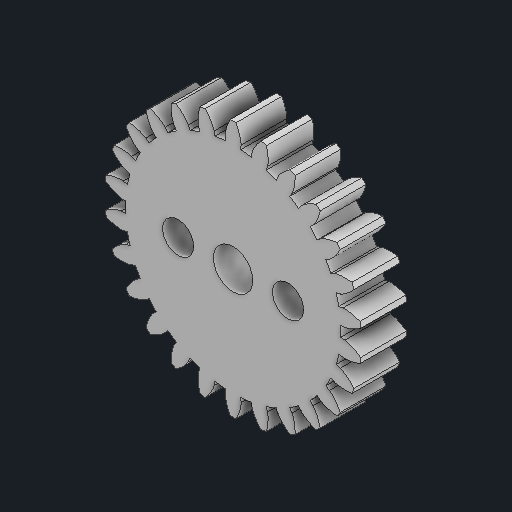
# Autodesk Inventor part: P2-03 Right driven gear 26 teeth
Saved by Autodesk Inventor 2027.1 (Build 311270010, 270A)
## iProperties
Created: 2026-10-21
Part Number: P2-03 Right driven gear 26 teeth
Material: Generic
Document SubType Name: Modeling
Designer: anshi
Mass: 2.32572 g
Surface Area: 20.3436 cm^2
Volume: 2.32572 cm^3
Density: 1 g/cm^3
Appearance: Default
Author: anshi
Autodesk Inventor part; units mm, degrees
ref_plane "YZ Plane" through (0, 0, 0) normal (1, 0, 0) x (0, 1, 0)
ref_plane "XZ Plane" through (0, 0, 0) normal (0, 1, 0) x (-1, 0, 0)
ref_plane "XY Plane" through (0, 0, 0) normal (0, 0, 1) x (1, 0, 0)
sketch "Dimensioned base profile" plane through (0, 0, 0) normal (0, 0, 1) x (1, 0, 0)
  line L0 (11.7357, 0.5797) -> (12.2011, 0.6027)
  spline S0 degree 4 poles (12.2011, 0.6027) (12.209, 0.6028) (12.2485, 0.6066) (12.3141, 0.6172) (12.4241, 0.6414) (12.5388, 0.6724) (12.6782, 0.7169) (12.8402, 0.7771) (13.0239, 0.8551) (13.3144, 0.9948) (13.5707, 1.1408) (13.7787, 1.2746) (13.9317, 1.3813) knots 0 0 0 0 0 0.103317 0.164454 0.235729 0.315759 0.40363 0.498674 0.600371 0.708303 1 1 1 1 1
  arc A0 (13.9317, 1.3813) -> (13.8574, 1.9929) centre (0, 0) ccw
  spline S1 degree 4 poles (13.8574, 1.9929) (13.6835, 2.0597) (13.4498, 2.1397) (13.1663, 2.2199) (12.851, 2.2859) (12.6541, 2.3177) (12.4826, 2.3373) (12.3366, 2.3472) (12.2176, 2.35) (12.1048, 2.3474) (12.0382, 2.342) (11.9988, 2.3366) (11.9908, 2.3347) knots 0 0 0 0 0 0.291394 0.399224 0.500833 0.595807 0.683628 0.763634 0.834917 0.896108 1 1 1 1 1
  line L1 (11.9908, 2.3347) -> (11.5334, 2.2457)
  arc A1 (11.5334, 2.2457) -> (11.2559, 3.3714) centre (0, 0) ccw
  line L2 (11.2559, 3.3714) -> (11.7023, 3.5051)
  spline S2 degree 4 poles (11.7023, 3.5051) (11.7102, 3.5074) (11.7477, 3.5207) (11.8092, 3.5469) (11.9104, 3.5968) (12.0145, 3.6545) (12.1392, 3.7311) (12.282, 3.8282) (12.4416, 3.9478) (12.69, 4.1528) (12.9037, 4.3557) (13.0734, 4.5352) (13.1963, 4.6753) knots 0 0 0 0 0 0.103853 0.165057 0.23635 0.316361 0.404186 0.49916 0.60077 0.708601 1 1 1 1 1
  arc A2 (13.1963, 4.6753) -> (12.9778, 5.2513) centre (0, 0) ccw
  spline S3 degree 4 poles (12.9778, 5.2513) (12.7925, 5.2741) (12.5459, 5.2953) (12.2508, 5.3048) (11.9284, 5.2928) (11.7294, 5.2763) (11.558, 5.2542) (11.414, 5.2289) (11.2981, 5.2033) (11.1899, 5.1741) (11.1272, 5.1536) (11.0907, 5.1394) (11.0837, 5.1365) knots 0 0 0 0 0 0.292086 0.400157 0.501975 0.597116 0.685051 0.765101 0.836335 0.897338 1 1 1 1 1
  line L3 (11.0837, 5.1365) -> (10.6608, 4.9405)
  arc A3 (10.6608, 4.9405) -> (10.122, 5.9672) centre (0, 0) ccw
  line L4 (10.122, 5.9672) -> (10.5235, 6.2038)
  spline S4 degree 4 poles (10.5235, 6.2038) (10.5305, 6.2079) (10.5638, 6.2298) (10.6172, 6.2699) (10.7036, 6.3426) (10.7908, 6.4235) (10.8936, 6.5277) (11.009, 6.6562) (11.1353, 6.8106) (11.3275, 7.069) (11.4864, 7.3171) (11.6082, 7.5321) (11.694, 7.6975) knots 0 0 0 0 0 0.10386 0.165064 0.236357 0.316368 0.404191 0.499165 0.600774 0.708603 1 1 1 1 1
  arc A4 (11.694, 7.6975) -> (11.344, 8.2045) centre (0, 0) ccw
  spline S5 degree 4 poles (11.344, 8.2045) (11.1586, 8.1822) (10.9139, 8.1436) (10.6251, 8.0821) (10.3149, 7.9932) (10.1256, 7.9295) (9.9645, 7.867) (9.8307, 7.808) (9.7244, 7.7554) (9.6264, 7.7014) (9.5704, 7.6665) (9.5385, 7.6442) (9.5323, 7.6397) knots 0 0 0 0 0 0.29219 0.400296 0.502144 0.597307 0.685255 0.765304 0.83652 0.89748 1 1 1 1 1
  line L5 (9.5323, 7.6397) -> (9.1687, 7.3483)
  arc A5 (9.1687, 7.3483) -> (8.3999, 8.2161) centre (0, 0) ccw
  line L6 (8.3999, 8.2161) -> (8.733, 8.542)
  spline S6 degree 4 poles (8.733, 8.542) (8.7389, 8.5476) (8.7659, 8.5768) (8.8082, 8.6286) (8.8747, 8.7199) (8.94, 8.8193) (9.0149, 8.945) (9.0962, 9.0974) (9.1819, 9.2775) (9.3066, 9.5744) (9.4015, 9.8534) (9.4684, 10.0912) (9.512, 10.2724) knots 0 0 0 0 0 0.10386 0.165064 0.236356 0.316367 0.404191 0.499164 0.600774 0.708603 1 1 1 1 1
  arc A6 (9.512, 10.2724) -> (9.0509, 10.6809) centre (0, 0) ccw
  spline S7 degree 4 poles (9.0509, 10.6809) (8.8761, 10.6147) (8.6477, 10.5185) (8.3819, 10.3893) (8.1018, 10.2286) (7.9332, 10.1213) (7.7918, 10.0221) (7.676, 9.9328) (7.5854, 9.8564) (7.5034, 9.7808) (7.4575, 9.7337) (7.4319, 9.7048) (7.427, 9.699) knots 0 0 0 0 0 0.292397 0.400574 0.50248 0.597687 0.68566 0.765709 0.836892 0.897771 1 1 1 1 1
  line L7 (7.427, 9.699) -> (7.1437, 9.329)
  arc A7 (7.1437, 9.329) -> (6.1895, 9.9876) centre (0, 0) ccw
  line L8 (6.1895, 9.9876) -> (6.435, 10.3837)
  spline S8 degree 4 poles (6.435, 10.3837) (6.4394, 10.3906) (6.4587, 10.4253) (6.4874, 10.4857) (6.5301, 10.5902) (6.5698, 10.7024) (6.6123, 10.8424) (6.6548, 11.0098) (6.6949, 11.2052) (6.7449, 11.5234) (6.7703, 11.8169) (6.7782, 12.0639) (6.7773, 12.2502) knots 0 0 0 0 0 0.103831 0.16503 0.236321 0.316331 0.404157 0.499134 0.600748 0.708584 1 1 1 1 1
  arc A8 (6.7773, 12.2502) -> (6.2318, 12.5365) centre (0, 0) ccw
  spline S9 degree 4 poles (6.2318, 12.5365) (6.0775, 12.4303) (5.8783, 12.2819) (5.6505, 12.0925) (5.4166, 11.8691) (5.2783, 11.7244) (5.1646, 11.5942) (5.0737, 11.4798) (5.0042, 11.3841) (4.9432, 11.2915) (4.9103, 11.2351) (4.8931, 11.2013) (4.8901, 11.1945) knots 0 0 0 0 0 0.292948 0.401308 0.503368 0.59869 0.686732 0.766794 0.837914 0.898616 1 1 1 1 1
  line L9 (4.8901, 11.1945) -> (4.7036, 10.7675)
  arc A9 (4.7036, 10.7675) -> (3.6195, 11.1786) centre (0, 0) ccw
  line L10 (3.6195, 11.1786) -> (3.763, 11.622)
  spline S10 degree 4 poles (3.763, 11.622) (3.7657, 11.6296) (3.7762, 11.668) (3.7897, 11.7334) (3.8062, 11.845) (3.8179, 11.9634) (3.8257, 12.1096) (3.8268, 12.2823) (3.819, 12.4816) (3.7914, 12.8026) (3.7456, 13.0937) (3.6942, 13.3355) (3.6487, 13.5162) knots 0 0 0 0 0 0.10378 0.164969 0.236254 0.316264 0.404092 0.499076 0.600699 0.708547 1 1 1 1 1
  arc A10 (3.6487, 13.5162) -> (3.0505, 13.6636) centre (0, 0) ccw
  spline S11 degree 4 poles (3.0505, 13.6636) (2.9262, 13.5237) (2.7683, 13.3323) (2.5925, 13.0943) (2.4188, 12.8216) (2.3193, 12.6482) (2.24, 12.4945) (2.1791, 12.3617) (2.1345, 12.252) (2.0974, 12.147) (2.0789, 12.0842) (2.0703, 12.0468) (2.069, 12.0395) knots 0 0 0 0 0 0.292693 0.400968 0.502958 0.59823 0.686248 0.766317 0.837488 0.898305 1 1 1 1 1
  line L11 (2.069, 12.0395) -> (1.9901, 11.5802)
  arc A11 (1.9901, 11.5802) -> (0.8391, 11.72) centre (0, 0) ccw
  line L12 (0.8391, 11.72) -> (0.8724, 12.1848)
  spline S12 degree 4 poles (0.8724, 12.1848) (0.8731, 12.1929) (0.874, 12.2327) (0.8714, 12.2994) (0.8606, 12.4118) (0.8436, 12.5295) (0.8163, 12.6733) (0.7761, 12.8413) (0.7208, 13.0329) (0.6172, 13.3379) (0.5032, 13.6097) (0.3955, 13.8321) (0.308, 13.9966) knots 0 0 0 0 0 0.103807 0.165003 0.236292 0.316303 0.404131 0.499111 0.600729 0.708569 1 1 1 1 1
  arc A12 (0.308, 13.9966) -> (-0.308, 13.9966) centre (0, 0) ccw
  spline S13 degree 4 poles (-0.308, 13.9966) (-0.3956, 13.831) (-0.5034, 13.6073) (-0.6175, 13.3341) (-0.7212, 13.0277) (-0.7766, 12.8355) (-0.8168, 12.6673) (-0.8441, 12.5237) (-0.8611, 12.4066) (-0.8717, 12.2958) (-0.8743, 12.2305) (-0.8732, 12.1921) (-0.8724, 12.1848) knots 0 0 0 0 0 0.292789 0.401092 0.503102 0.598385 0.686404 0.766465 0.837615 0.898399 1 1 1 1 1
  line L13 (-0.8724, 12.1848) -> (-0.8391, 11.72)
  arc A13 (-0.8391, 11.72) -> (-1.9901, 11.5802) centre (0, 0) ccw
  line L14 (-1.9901, 11.5802) -> (-2.069, 12.0395)
  spline S14 degree 4 poles (-2.069, 12.0395) (-2.0704, 12.0475) (-2.0791, 12.0864) (-2.0977, 12.1506) (-2.1351, 12.2571) (-2.1798, 12.3673) (-2.2408, 12.5004) (-2.32, 12.6538) (-2.4195, 12.8267) (-2.593, 13.098) (-2.7686, 13.3346) (-2.9263, 13.5248) (-3.0505, 13.6636) knots 0 0 0 0 0 0.103844 0.165049 0.236343 0.316356 0.404182 0.499158 0.600769 0.7086 1 1 1 1 1
  arc A14 (-3.0505, 13.6636) -> (-3.6487, 13.5162) centre (0, 0) ccw
  spline S15 degree 4 poles (-3.6487, 13.5162) (-3.6942, 13.3348) (-3.7456, 13.0922) (-3.7913, 12.8001) (-3.8189, 12.4782) (-3.8268, 12.2785) (-3.8256, 12.1056) (-3.8178, 11.9595) (-3.8062, 11.8415) (-3.7898, 11.7309) (-3.7764, 11.6665) (-3.7659, 11.6289) (-3.763, 11.622) knots 0 0 0 0 0 0.292364 0.400522 0.502409 0.597597 0.685557 0.765608 0.836813 0.897752 1 1 1 1 1
  line L15 (-3.763, 11.622) -> (-3.6195, 11.1786)
  arc A15 (-3.6195, 11.1786) -> (-4.7036, 10.7675) centre (0, 0) ccw
  line L16 (-4.7036, 10.7675) -> (-4.8901, 11.1945)
  spline S16 degree 4 poles (-4.8901, 11.1945) (-4.8935, 11.2019) (-4.9112, 11.2375) (-4.9447, 11.2953) (-5.0065, 11.3897) (-5.0763, 11.4861) (-5.1673, 11.6007) (-5.281, 11.7307) (-5.4189, 11.8748) (-5.6523, 12.0967) (-5.8794, 12.2845) (-6.078, 12.4314) (-6.2318, 12.5365) knots 0 0 0 0 0 0.103783 0.164983 0.236278 0.316296 0.404129 0.499113 0.600734 0.708575 1 1 1 1 1
  arc A16 (-6.2318, 12.5365) -> (-6.7773, 12.2502) centre (0, 0) ccw
  spline S17 degree 4 poles (-6.7773, 12.2502) (-6.7783, 12.0637) (-6.7704, 11.8165) (-6.7451, 11.5226) (-6.6952, 11.2041) (-6.6551, 11.0085) (-6.6127, 10.8411) (-6.5701, 10.7011) (-6.5305, 10.589) (-6.4878, 10.4848) (-6.459, 10.4248) (-6.4396, 10.3902) (-6.435, 10.3837) knots 0 0 0 0 0 0.29167 0.399589 0.501273 0.596303 0.68416 0.764178 0.835443 0.896575 1 1 1 1 1
  line L17 (-6.435, 10.3837) -> (-6.1895, 9.9876)
  arc A17 (-6.1895, 9.9876) -> (-7.1437, 9.329) centre (0, 0) ccw
  line L18 (-7.1437, 9.329) -> (-7.427, 9.699)
  spline S18 degree 4 poles (-7.427, 9.699) (-7.4321, 9.7052) (-7.4579, 9.7355) (-7.5042, 9.7835) (-7.5868, 9.8603) (-7.6776, 9.9371) (-7.7935, 10.0266) (-7.9349, 10.1257) (-8.1033, 10.2325) (-8.383, 10.3923) (-8.6484, 10.5203) (-8.8764, 10.6155) (-9.0509, 10.6809) knots 0 0 0 0 0 0.103669 0.164859 0.236155 0.31618 0.404024 0.499024 0.600662 0.708522 1 1 1 1 1
  arc A18 (-9.0509, 10.6809) -> (-9.512, 10.2724) centre (0, 0) ccw
  spline S19 degree 4 poles (-9.512, 10.2724) (-9.4684, 10.0912) (-9.4015, 9.8534) (-9.3067, 9.5744) (-9.1819, 9.2774) (-9.0962, 9.0973) (-9.015, 8.9449) (-8.9401, 8.8192) (-8.8748, 8.7198) (-8.8083, 8.6285) (-8.766, 8.5768) (-8.7389, 8.5476) (-8.733, 8.542) knots 0 0 0 0 0 0.291403 0.399234 0.500844 0.595818 0.683642 0.763651 0.834942 0.896144 1 1 1 1 1
  line L19 (-8.733, 8.542) -> (-8.3999, 8.2161)
  arc A19 (-8.3999, 8.2161) -> (-9.1687, 7.3483) centre (0, 0) ccw
  line L20 (-9.1687, 7.3483) -> (-9.5323, 7.6397)
  spline S20 degree 4 poles (-9.5323, 7.6397) (-9.5388, 7.6443) (-9.571, 7.6675) (-9.6275, 7.7029) (-9.726, 7.7576) (-9.8325, 7.8104) (-9.9664, 7.8696) (-10.1274, 7.932) (-10.3166, 7.9955) (-10.6264, 8.0838) (-10.9147, 8.1447) (-11.1589, 8.1827) (-11.344, 8.2045) knots 0 0 0 0 0 0.103491 0.164665 0.235961 0.315996 0.403859 0.498882 0.600548 0.708439 1 1 1 1 1
  arc A20 (-11.344, 8.2045) -> (-11.694, 7.6975) centre (0, 0) ccw
  spline S21 degree 4 poles (-11.694, 7.6975) (-11.6081, 7.5322) (-11.486, 7.3173) (-11.3269, 7.0693) (-11.1345, 6.8109) (-11.0081, 6.6566) (-10.8927, 6.5282) (-10.7899, 6.424) (-10.7028, 6.3431) (-10.6165, 6.2703) (-10.5634, 6.2301) (-10.5302, 6.2082) (-10.5235, 6.2038) knots 0 0 0 0 0 0.291491 0.399357 0.501 0.596005 0.683854 0.763882 0.835179 0.896367 1 1 1 1 1
  line L21 (-10.5235, 6.2038) -> (-10.122, 5.9672)
  arc A21 (-10.122, 5.9672) -> (-10.6608, 4.9405) centre (0, 0) ccw
  line L22 (-10.6608, 4.9405) -> (-11.0837, 5.1365)
  spline S22 degree 4 poles (-11.0837, 5.1365) (-11.091, 5.1395) (-11.1278, 5.1544) (-11.1911, 5.1752) (-11.2998, 5.2048) (-11.4159, 5.2306) (-11.56, 5.256) (-11.7313, 5.278) (-11.9302, 5.2944) (-12.2521, 5.306) (-12.5467, 5.2961) (-12.7929, 5.2745) (-12.9778, 5.2513) knots 0 0 0 0 0 0.103496 0.164668 0.235961 0.315994 0.403855 0.498878 0.600543 0.708435 1 1 1 1 1
  arc A22 (-12.9778, 5.2513) -> (-13.1963, 4.6753) centre (0, 0) ccw
  spline S23 degree 4 poles (-13.1963, 4.6753) (-13.0729, 4.5355) (-12.9024, 4.3564) (-12.688, 4.154) (-12.4389, 3.9495) (-12.279, 3.83) (-12.136, 3.733) (-12.0113, 3.6565) (-11.9075, 3.5987) (-11.8069, 3.5487) (-11.7464, 3.522) (-11.7091, 3.5086) (-11.7023, 3.5051) knots 0 0 0 0 0 0.291864 0.399868 0.501639 0.596753 0.684688 0.764768 0.83607 0.897187 1 1 1 1 1
  line L23 (-11.7023, 3.5051) -> (-11.2559, 3.3714)
  arc A23 (-11.2559, 3.3714) -> (-11.5334, 2.2457) centre (0, 0) ccw
  line L24 (-11.5334, 2.2457) -> (-11.9908, 2.3347)
  spline S24 degree 4 poles (-11.9908, 2.3347) (-11.9985, 2.3358) (-12.0378, 2.3414) (-12.1041, 2.3464) (-12.2167, 2.3491) (-12.3355, 2.3464) (-12.4815, 2.3365) (-12.6531, 2.3169) (-12.8501, 2.2853) (-13.1656, 2.2195) (-13.4494, 2.1395) (-13.6834, 2.0596) (-13.8574, 1.9929) knots 0 0 0 0 0 0.103266 0.164415 0.235705 0.31575 0.403633 0.498685 0.600387 0.708319 1 1 1 1 1
  arc A24 (-13.8574, 1.9929) -> (-13.9317, 1.3813) centre (0, 0) ccw
  spline S25 degree 4 poles (-13.9317, 1.3813) (-13.7781, 1.2751) (-13.5694, 1.1419) (-13.3123, 0.9966) (-13.0211, 0.8575) (-12.8371, 0.7798) (-12.675, 0.7198) (-12.5356, 0.6753) (-12.4212, 0.6441) (-12.3119, 0.6197) (-12.2474, 0.6084) (-12.2081, 0.6042) (-12.2011, 0.6027) knots 0 0 0 0 0 0.292307 0.400465 0.502368 0.597589 0.685599 0.765713 0.836996 0.898019 1 1 1 1 1
  line L25 (-12.2011, 0.6027) -> (-11.7357, 0.5797)
  arc A25 (-11.7357, 0.5797) -> (-11.7357, -0.5797) centre (0, 0) ccw
  line L26 (-11.7357, -0.5797) -> (-12.2011, -0.6027)
  spline S26 degree 4 poles (-12.2011, -0.6027) (-12.2088, -0.6037) (-12.2483, -0.6077) (-12.3138, -0.6187) (-12.4237, -0.6431) (-12.5383, -0.6742) (-12.6778, -0.7187) (-12.8397, -0.7788) (-13.0235, -0.8566) (-13.3141, -0.9959) (-13.5705, -1.1415) (-13.7786, -1.2749) (-13.9317, -1.3813) knots 0 0 0 0 0 0.103188 0.164331 0.235624 0.315674 0.403567 0.498629 0.600343 0.708288 1 1 1 1 1
  arc A26 (-13.9317, -1.3813) -> (-13.8574, -1.9929) centre (0, 0) ccw
  spline S27 degree 4 poles (-13.8574, -1.9929) (-13.6831, -2.0601) (-13.4487, -2.1405) (-13.1646, -2.2212) (-12.8487, -2.2876) (-12.6514, -2.3195) (-12.4797, -2.3392) (-12.3337, -2.3491) (-12.215, -2.3517) (-12.1028, -2.3488) (-12.0371, -2.343) (-11.9979, -2.3372) (-11.9908, -2.3347) knots 0 0 0 0 0 0.292101 0.400169 0.501981 0.597114 0.685046 0.765101 0.836358 0.897413 1 1 1 1 1
  line L27 (-11.9908, -2.3347) -> (-11.5334, -2.2457)
  arc A27 (-11.5334, -2.2457) -> (-11.2559, -3.3714) centre (0, 0) ccw
  line L28 (-11.2559, -3.3714) -> (-11.7023, -3.5051)
  spline S28 degree 4 poles (-11.7023, -3.5051) (-11.7074, -3.5058) (-11.7442, -3.519) (-11.8016, -3.5435) (-11.9002, -3.5923) (-12.0031, -3.6494) (-12.1278, -3.726) (-12.2711, -3.8233) (-12.4319, -3.9435) (-12.6829, -4.1496) (-12.8993, -4.3537) (-13.0715, -4.5343) (-13.1963, -4.6753) knots 0 0 0 0 0 0.097727 0.158305 0.22951 0.309802 0.398187 0.493943 0.596511 0.705442 1 1 1 1 1
  arc A28 (-13.1963, -4.6753) -> (-12.9778, -5.2513) centre (0, 0) ccw
  spline S29 degree 4 poles (-12.9778, -5.2513) (-12.7923, -5.2747) (-12.5453, -5.2965) (-12.2499, -5.3067) (-11.9271, -5.2954) (-11.7278, -5.2791) (-11.5564, -5.2571) (-11.4122, -5.2318) (-11.2965, -5.2059) (-11.1885, -5.1763) (-11.1264, -5.1552) (-11.0898, -5.1403) (-11.0837, -5.1365) knots 0 0 0 0 0 0.292369 0.400531 0.502425 0.597627 0.685608 0.765689 0.836938 0.897938 1 1 1 1 1
  line L29 (-11.0837, -5.1365) -> (-10.6608, -4.9405)
  arc A29 (-10.6608, -4.9405) -> (-10.122, -5.9672) centre (0, 0) ccw
  line L30 (-10.122, -5.9672) -> (-10.5235, -6.2038)
  spline S30 degree 4 poles (-10.5235, -6.2038) (-10.5278, -6.2051) (-10.5603, -6.2269) (-10.6094, -6.2638) (-10.6929, -6.3344) (-10.7789, -6.4143) (-10.8817, -6.5185) (-10.9976, -6.6474) (-11.1252, -6.8027) (-11.32, -7.0633) (-11.4818, -7.3136) (-11.6062, -7.5305) (-11.694, -7.6975) knots 0 0 0 0 0 0.096349 0.156803 0.228 0.308361 0.396873 0.492802 0.595581 0.704753 1 1 1 1 1
  arc A30 (-11.694, -7.6975) -> (-11.344, -8.2045) centre (0, 0) ccw
  spline S31 degree 4 poles (-11.344, -8.2045) (-11.1583, -8.1826) (-10.9132, -8.1444) (-10.6239, -8.0833) (-10.3132, -7.9947) (-10.1236, -7.9311) (-9.9624, -7.8687) (-9.8285, -7.8096) (-9.7224, -7.7569) (-9.6247, -7.7025) (-9.5695, -7.6675) (-9.5375, -7.6444) (-9.5323, -7.6397) knots 0 0 0 0 0 0.292525 0.400746 0.502694 0.597942 0.685959 0.766062 0.837313 0.898283 1 1 1 1 1
  line L31 (-9.5323, -7.6397) -> (-9.1687, -7.3483)
  arc A31 (-9.1687, -7.3483) -> (-8.3999, -8.2161) centre (0, 0) ccw
  line L32 (-8.3999, -8.2161) -> (-8.733, -8.542)
  spline S32 degree 4 poles (-8.733, -8.542) (-8.7356, -8.5466) (-8.7619, -8.5756) (-8.8005, -8.6251) (-8.865, -8.7144) (-8.9294, -8.8131) (-9.0043, -8.9389) (-9.086, -9.0914) (-9.1729, -9.2722) (-9.2999, -9.5705) (-9.3974, -9.851) (-9.4666, -10.0902) (-9.512, -10.2724) knots 0 0 0 0 0 0.098234 0.158888 0.230131 0.310429 0.39879 0.494491 0.596978 0.705801 1 1 1 1 1
  arc A32 (-9.512, -10.2724) -> (-9.0509, -10.6809) centre (0, 0) ccw
  spline S33 degree 4 poles (-9.0509, -10.6809) (-8.876, -10.6154) (-8.6475, -10.5201) (-8.3816, -10.3919) (-8.1013, -10.232) (-7.9327, -10.125) (-7.7911, -10.0259) (-7.6753, -9.9365) (-7.5847, -9.8597) (-7.5025, -9.7832) (-7.4568, -9.7354) (-7.4313, -9.7052) (-7.427, -9.699) knots 0 0 0 0 0 0.292006 0.400046 0.501836 0.596954 0.684879 0.764936 0.836202 0.897278 1 1 1 1 1
  line L33 (-7.427, -9.699) -> (-7.1437, -9.329)
  arc A33 (-7.1437, -9.329) -> (-6.1895, -9.9876) centre (0, 0) ccw
  line L34 (-6.1895, -9.9876) -> (-6.435, -10.3837)
  spline S34 degree 4 poles (-6.435, -10.3837) (-6.4362, -10.3891) (-6.4549, -10.4235) (-6.4806, -10.4812) (-6.5219, -10.5835) (-6.5607, -10.6948) (-6.6034, -10.8348) (-6.6462, -11.0025) (-6.6873, -11.1987) (-6.7393, -11.5185) (-6.7668, -11.814) (-6.7767, -12.0626) (-6.7773, -12.2502) knots 0 0 0 0 0 0.098614 0.159305 0.230554 0.310837 0.399164 0.494819 0.597247 0.706002 1 1 1 1 1
  arc A34 (-6.7773, -12.2502) -> (-6.2318, -12.5365) centre (0, 0) ccw
  spline S35 degree 4 poles (-6.2318, -12.5365) (-6.0778, -12.4312) (-5.8789, -12.2839) (-5.6516, -12.0959) (-5.418, -11.8736) (-5.2798, -11.7294) (-5.1662, -11.5993) (-5.0751, -11.4847) (-5.0054, -11.3885) (-4.9439, -11.2944) (-4.9107, -11.2371) (-4.8931, -11.2016) (-4.8901, -11.1945) knots 0 0 0 0 0 0.291864 0.399856 0.501606 0.596695 0.6846 0.76465 0.835926 0.897032 1 1 1 1 1
  line L35 (-4.8901, -11.1945) -> (-4.7036, -10.7675)
  arc A35 (-4.7036, -10.7675) -> (-3.6195, -11.1786) centre (0, 0) ccw
  line L36 (-3.6195, -11.1786) -> (-3.763, -11.622)
  spline S36 degree 4 poles (-3.763, -11.622) (-3.763, -11.6273) (-3.7729, -11.6652) (-3.7841, -11.7271) (-3.7997, -11.8362) (-3.8107, -11.9535) (-3.8186, -12.0997) (-3.8201, -12.2728) (-3.813, -12.4731) (-3.7869, -12.7963) (-3.743, -13.0899) (-3.6931, -13.3338) (-3.6487, -13.5162) knots 0 0 0 0 0 0.098331 0.158995 0.23024 0.310535 0.398887 0.494578 0.597049 0.705854 1 1 1 1 1
  arc A36 (-3.6487, -13.5162) -> (-3.0505, -13.6636) centre (0, 0) ccw
  spline S37 degree 4 poles (-3.0505, -13.6636) (-2.9263, -13.5244) (-2.7686, -13.3338) (-2.5929, -13.0968) (-2.4194, -12.825) (-2.3199, -12.6519) (-2.2407, -12.4984) (-2.1797, -12.3654) (-2.135, -12.2553) (-2.0977, -12.1492) (-2.0791, -12.0857) (-2.0704, -12.047) (-2.069, -12.0395) knots 0 0 0 0 0 0.291857 0.399849 0.501601 0.596692 0.684601 0.764656 0.835936 0.897045 1 1 1 1 1
  line L37 (-2.069, -12.0395) -> (-1.9901, -11.5802)
  arc A37 (-1.9901, -11.5802) -> (-0.8391, -11.72) centre (0, 0) ccw
  line L38 (-0.8391, -11.72) -> (-0.8724, -12.1848)
  spline S38 degree 4 poles (-0.8724, -12.1848) (-0.8712, -12.1906) (-0.8717, -12.2298) (-0.8678, -12.2934) (-0.8568, -12.4036) (-0.8395, -12.5204) (-0.8122, -12.6642) (-0.7722, -12.8325) (-0.7173, -13.0251) (-0.6146, -13.3321) (-0.5016, -13.6061) (-0.3948, -13.8305) (-0.308, -13.9966) knots 0 0 0 0 0 0.099467 0.160239 0.231494 0.311733 0.39998 0.495525 0.597821 0.706426 1 1 1 1 1
  arc A38 (-0.308, -13.9966) -> (0.308, -13.9966) centre (0, 0) ccw
  spline S39 degree 4 poles (0.308, -13.9966) (0.3953, -13.8317) (0.5028, -13.6087) (0.6166, -13.3364) (0.72, -13.0309) (0.7752, -12.839) (0.8153, -12.671) (0.8427, -12.5272) (0.8598, -12.4097) (0.8706, -12.2979) (0.8735, -12.2319) (0.8727, -12.1923) (0.8724, -12.1848) knots 0 0 0 0 0 0.291972 0.400004 0.501792 0.596912 0.684843 0.764908 0.836185 0.897271 1 1 1 1 1
  line L39 (0.8724, -12.1848) -> (0.8391, -11.72)
  arc A39 (0.8391, -11.72) -> (1.9901, -11.5802) centre (0, 0) ccw
  line L40 (1.9901, -11.5802) -> (2.069, -12.0395)
  spline S40 degree 4 poles (2.069, -12.0395) (2.0713, -12.0455) (2.0801, -12.0838) (2.099, -12.1454) (2.1362, -12.2502) (2.1809, -12.3597) (2.2419, -12.4928) (2.321, -12.6466) (2.4204, -12.8202) (2.5936, -13.0932) (2.769, -13.3317) (2.9265, -13.5235) (3.0505, -13.6636) knots 0 0 0 0 0 0.100504 0.161375 0.232637 0.312821 0.400967 0.496378 0.598513 0.706936 1 1 1 1 1
  arc A40 (3.0505, -13.6636) -> (3.6487, -13.5162) centre (0, 0) ccw
  spline S41 degree 4 poles (3.6487, -13.5162) (3.6937, -13.335) (3.7445, -13.0927) (3.7894, -12.8008) (3.8164, -12.4793) (3.8239, -12.2797) (3.8226, -12.1069) (3.8147, -11.9608) (3.8033, -11.8427) (3.7872, -11.7318) (3.7746, -11.6673) (3.7645, -11.6291) (3.763, -11.622) knots 0 0 0 0 0 0.2922 0.400317 0.502181 0.597369 0.685351 0.765448 0.836727 0.897769 1 1 1 1 1
  line L41 (3.763, -11.622) -> (3.6195, -11.1786)
  arc A41 (3.6195, -11.1786) -> (4.7036, -10.7675) centre (0, 0) ccw
  line L42 (4.7036, -10.7675) -> (4.8901, -11.1945)
  spline S42 degree 4 poles (4.8901, -11.1945) (4.8939, -11.2009) (4.9117, -11.2362) (4.9452, -11.293) (5.0068, -11.3868) (5.0766, -11.4828) (5.1676, -11.5974) (5.2812, -11.7276) (5.4191, -11.872) (5.6524, -12.0947) (5.8794, -12.2832) (6.078, -12.4308) (6.2318, -12.5365) knots 0 0 0 0 0 0.102517 0.163593 0.23488 0.314966 0.402923 0.498074 0.599893 0.707956 1 1 1 1 1
  arc A42 (6.2318, -12.5365) -> (6.7773, -12.2502) centre (0, 0) ccw
  spline S43 degree 4 poles (6.7773, -12.2502) (6.7781, -12.0639) (6.7699, -11.8169) (6.7443, -11.5234) (6.694, -11.2052) (6.6538, -11.0098) (6.6113, -10.8424) (6.5687, -10.7024) (6.5291, -10.5902) (6.4866, -10.4858) (6.4582, -10.4255) (6.439, -10.3907) (6.435, -10.3837) knots 0 0 0 0 0 0.291508 0.399379 0.501027 0.596034 0.683885 0.763912 0.835207 0.896392 1 1 1 1 1
  line L43 (6.435, -10.3837) -> (6.1895, -9.9876)
  arc A43 (6.1895, -9.9876) -> (7.1437, -9.329) centre (0, 0) ccw
  line L44 (7.1437, -9.329) -> (7.427, -9.699)
  spline S44 degree 4 poles (7.427, -9.699) (7.4322, -9.704) (7.4579, -9.734) (7.5039, -9.7809) (7.586, -9.857) (7.6767, -9.9335) (7.7925, -10.023) (7.9339, -10.1222) (8.1025, -10.2295) (8.3824, -10.3901) (8.648, -10.5189) (8.8762, -10.6149) (9.0509, -10.6809) knots 0 0 0 0 0 0.102138 0.163175 0.234457 0.314561 0.402554 0.497754 0.599633 0.707764 1 1 1 1 1
  arc A44 (9.0509, -10.6809) -> (9.512, -10.2724) centre (0, 0) ccw
  spline S45 degree 4 poles (9.512, -10.2724) (9.4679, -10.0911) (9.4004, -9.8531) (9.3048, -9.574) (9.1794, -9.2769) (9.0934, -9.0967) (9.012, -8.9444) (8.9371, -8.8186) (8.872, -8.7193) (8.8061, -8.6284) (8.7647, -8.5769) (8.7379, -8.5477) (8.733, -8.542) knots 0 0 0 0 0 0.291937 0.39996 0.501744 0.596864 0.684798 0.764871 0.836157 0.897254 1 1 1 1 1
  line L45 (8.733, -8.542) -> (8.3999, -8.2161)
  arc A45 (8.3999, -8.2161) -> (9.1687, -7.3483) centre (0, 0) ccw
  line L46 (9.1687, -7.3483) -> (9.5323, -7.6397)
  spline S46 degree 4 poles (9.5323, -7.6397) (9.5387, -7.6448) (9.5709, -7.6681) (9.6274, -7.7038) (9.7261, -7.7588) (9.8326, -7.8117) (9.9665, -7.8708) (10.1275, -7.9332) (10.3167, -7.9965) (10.6265, -8.0846) (10.9148, -8.1452) (11.159, -8.1829) (11.344, -8.2045) knots 0 0 0 0 0 0.103849 0.165054 0.236348 0.31636 0.404185 0.499161 0.600771 0.708602 1 1 1 1 1
  arc A46 (11.344, -8.2045) -> (11.694, -7.6975) centre (0, 0) ccw
  spline S47 degree 4 poles (11.694, -7.6975) (11.608, -7.5321) (11.4859, -7.3173) (11.3267, -7.0693) (11.1342, -6.8109) (11.0078, -6.6566) (10.8923, -6.5281) (10.7895, -6.4239) (10.7024, -6.343) (10.6163, -6.2703) (10.5632, -6.2301) (10.5301, -6.2082) (10.5235, -6.2038) knots 0 0 0 0 0 0.291569 0.399462 0.50113 0.596155 0.684019 0.764055 0.83535 0.896523 1 1 1 1 1
  line L47 (10.5235, -6.2038) -> (10.122, -5.9672)
  arc A47 (10.122, -5.9672) -> (10.6608, -4.9405) centre (0, 0) ccw
  line L48 (10.6608, -4.9405) -> (11.0837, -5.1365)
  spline S48 degree 4 poles (11.0837, -5.1365) (11.0911, -5.1396) (11.1279, -5.1545) (11.1913, -5.1755) (11.3002, -5.2052) (11.4163, -5.231) (11.5604, -5.2564) (11.7317, -5.2784) (11.9305, -5.2948) (12.2524, -5.3062) (12.5469, -5.2962) (12.793, -5.2745) (12.9778, -5.2513) knots 0 0 0 0 0 0.103712 0.164907 0.236202 0.316225 0.404065 0.499059 0.600691 0.708543 1 1 1 1 1
  arc A48 (12.9778, -5.2513) -> (13.1963, -4.6753) centre (0, 0) ccw
  spline S49 degree 4 poles (13.1963, -4.6753) (13.0733, -4.5352) (12.9033, -4.3558) (12.6894, -4.153) (12.4407, -3.9481) (12.281, -3.8285) (12.1382, -3.7314) (12.0135, -3.6549) (11.9095, -3.5972) (11.8085, -3.5472) (11.7473, -3.521) (11.7099, -3.5076) (11.7023, -3.5051) knots 0 0 0 0 0 0.291576 0.39947 0.501138 0.596162 0.684024 0.764057 0.835348 0.896518 1 1 1 1 1
  line L49 (11.7023, -3.5051) -> (11.2559, -3.3714)
  arc A49 (11.2559, -3.3714) -> (11.5334, -2.2457) centre (0, 0) ccw
  line L50 (11.5334, -2.2457) -> (11.9908, -2.3347)
  spline S50 degree 4 poles (11.9908, -2.3347) (11.9987, -2.3365) (12.038, -2.3423) (12.1046, -2.3478) (12.2174, -2.3507) (12.3363, -2.3481) (12.4823, -2.3382) (12.6539, -2.3185) (12.8508, -2.2867) (13.1662, -2.2206) (13.4497, -2.1401) (13.6835, -2.0599) (13.8574, -1.9929) knots 0 0 0 0 0 0.103742 0.164925 0.236208 0.316219 0.40405 0.499039 0.600669 0.708524 1 1 1 1 1
  arc A50 (13.8574, -1.9929) -> (13.9317, -1.3813) centre (0, 0) ccw
  spline S51 degree 4 poles (13.9317, -1.3813) (13.7788, -1.2748) (13.571, -1.1412) (13.3149, -0.9955) (13.0246, -0.8561) (12.841, -0.7782) (12.6791, -0.7181) (12.5396, -0.6736) (12.4248, -0.6425) (12.3146, -0.6182) (12.2487, -0.6073) (12.2092, -0.6034) (12.2011, -0.6027) knots 0 0 0 0 0 0.291442 0.399289 0.500916 0.595906 0.683744 0.763765 0.835062 0.89626 1 1 1 1 1
  line L51 (12.2011, -0.6027) -> (11.7357, -0.5797)
  arc A51 (11.7357, -0.5797) -> (11.7357, 0.5797) centre (0, 0) ccw
  circle A52 centre (0, 0) radius 2.15
  circle A53 centre (-6, 0) radius 1.7
  circle A54 centre (6, 0) radius 1.7
  point P0 (12.214, 0.6036)
  point P1 (12.2533, 0.6083)
  point P2 (12.3185, 0.6192)
  point P3 (12.4093, 0.6389)
  point P4 (12.5248, 0.6696)
  point P5 (12.6642, 0.7137)
  point P6 (12.8264, 0.7735)
  point P7 (13.0102, 0.8512)
  point P8 (13.2142, 0.9488)
  point P9 (13.4369, 1.0685)
  point P10 (13.6767, 1.212)
  point P11 (13.5696, 2.096)
  point P12 (13.3028, 2.1778)
  point P13 (13.0581, 2.2405)
  point P14 (12.8369, 2.2864)
  point P15 (12.64, 2.3178)
  point P16 (12.4682, 2.3371)
  point P17 (12.3224, 2.3466)
  point P18 (12.2028, 2.3489)
  point P19 (12.1098, 2.3465)
  point P20 (12.0435, 2.3417)
  point P21 (12.004, 2.337)
  point P22 (11.7149, 3.5093)
  point P23 (11.7522, 3.5235)
  point P24 (11.8132, 3.55)
  point P25 (11.8967, 3.5909)
  point P26 (12.0016, 3.6484)
  point P27 (12.1264, 3.7247)
  point P28 (12.2695, 3.8215)
  point P29 (12.4293, 3.9408)
  point P30 (12.6038, 4.0843)
  point P31 (12.7913, 4.2536)
  point P32 (12.9895, 4.4501)
  point P33 (12.673, 5.2819)
  point P34 (12.3937, 5.2968)
  point P35 (12.1406, 5.2987)
  point P36 (11.9144, 5.2899)
  point P37 (11.7155, 5.273)
  point P38 (11.5441, 5.2505)
  point P39 (11.4002, 5.2249)
  point P40 (11.2838, 5.1987)
  point P41 (11.1945, 5.1743)
  point P42 (11.1319, 5.1544)
  point P43 (11.0953, 5.1411)
  point P44 (10.5347, 6.2109)
  point P45 (10.5675, 6.2336)
  point P46 (10.6204, 6.2739)
  point P47 (10.6917, 6.3336)
  point P48 (10.7798, 6.4146)
  point P49 (10.8827, 6.5184)
  point P50 (10.9985, 6.6467)
  point P51 (11.125, 6.8008)
  point P52 (11.2602, 6.9819)
  point P53 (11.4016, 7.1911)
  point P54 (11.5471, 7.4294)
  point P55 (11.0406, 8.1611)
  point P56 (10.7657, 8.1086)
  point P57 (10.5195, 8.0498)
  point P58 (10.302, 7.987)
  point P59 (10.1129, 7.923)
  point P60 (9.9518, 7.8601)
  point P61 (9.8182, 7.8008)
  point P62 (9.7115, 7.7475)
  point P63 (9.6307, 7.7027)
  point P64 (9.5748, 7.6684)
  point P65 (9.5425, 7.6469)
  point P66 (8.7422, 8.5516)
  point P67 (8.7686, 8.5814)
  point P68 (8.8103, 8.6332)
  point P69 (8.8653, 8.7082)
  point P70 (8.9314, 8.8079)
  point P71 (9.0065, 8.9334)
  point P72 (9.0882, 9.0857)
  point P73 (9.1742, 9.2655)
  point P74 (9.2621, 9.4737)
  point P75 (9.3494, 9.7107)
  point P76 (9.4336, 9.9769)
  point P77 (8.7666, 10.5658)
  point P78 (8.5121, 10.4489)
  point P79 (8.2871, 10.3326)
  point P80 (8.0908, 10.2195)
  point P81 (7.9224, 10.112)
  point P82 (7.7811, 10.0123)
  point P83 (7.6656, 9.9228)
  point P84 (7.5748, 9.8457)
  point P85 (7.5071, 9.783)
  point P86 (7.4612, 9.7366)
  point P87 (7.4352, 9.7083)
  point P88 (6.4417, 10.3952)
  point P89 (6.4602, 10.4305)
  point P90 (6.4884, 10.4907)
  point P91 (6.5238, 10.5767)
  point P92 (6.5641, 10.6893)
  point P93 (6.607, 10.8291)
  point P94 (6.6499, 10.9965)
  point P95 (6.6904, 11.1917)
  point P96 (6.7258, 11.4149)
  point P97 (6.7538, 11.6659)
  point P98 (6.7718, 11.9445)
  point P99 (5.9826, 12.3564)
  point P100 (5.763, 12.1816)
  point P101 (5.5718, 12.0146)
  point P102 (5.408, 11.8576)
  point P103 (5.27, 11.7127)
  point P104 (5.1566, 11.5821)
  point P105 (5.0659, 11.4676)
  point P106 (4.9964, 11.371)
  point P107 (4.9461, 11.2941)
  point P108 (4.9131, 11.2384)
  point P109 (4.8953, 11.2053)
  point P110 (3.7669, 11.6347)
  point P111 (3.7765, 11.6733)
  point P112 (3.7894, 11.7384)
  point P113 (3.8033, 11.8304)
  point P114 (3.8155, 11.9494)
  point P115 (3.8237, 12.0954)
  point P116 (3.8253, 12.2682)
  point P117 (3.8178, 12.4675)
  point P118 (3.7988, 12.6927)
  point P119 (3.7659, 12.9431)
  point P120 (3.7166, 13.218)
  point P121 (2.8518, 13.4295)
  point P122 (2.6804, 13.2076)
  point P123 (2.5348, 12.9999)
  point P124 (2.4133, 12.8084)
  point P125 (2.314, 12.6349)
  point P126 (2.2351, 12.4809)
  point P127 (2.1745, 12.348)
  point P128 (2.1301, 12.2375)
  point P129 (2.0996, 12.1505)
  point P130 (2.0809, 12.0882)
  point P131 (2.0715, 12.0513)
  point P132 (0.873, 12.1981)
  point P133 (0.873, 12.2379)
  point P134 (0.8699, 12.3043)
  point P135 (0.8613, 12.3969)
  point P136 (0.8447, 12.5154)
  point P137 (0.8177, 12.6591)
  point P138 (0.7779, 12.8272)
  point P139 (0.723, 13.0189)
  point P140 (0.6507, 13.233)
  point P141 (0.5588, 13.4683)
  point P142 (0.4453, 13.7234)
  point P143 (-0.4454, 13.7217)
  point P144 (-0.5591, 13.4651)
  point P145 (-0.6511, 13.2286)
  point P146 (-0.7235, 13.0136)
  point P147 (-0.7785, 12.8213)
  point P148 (-0.8183, 12.6529)
  point P149 (-0.8453, 12.5093)
  point P150 (-0.8618, 12.3914)
  point P151 (-0.8703, 12.2997)
  point P152 (-0.8733, 12.2348)
  point P153 (-0.8731, 12.1968)
  point P154 (-2.0717, 12.0525)
  point P155 (-2.0813, 12.0912)
  point P156 (-2.1003, 12.1549)
  point P157 (-2.1308, 12.2428)
  point P158 (-2.1753, 12.3538)
  point P159 (-2.2359, 12.4869)
  point P160 (-2.3148, 12.6406)
  point P161 (-2.414, 12.8136)
  point P162 (-2.5353, 13.0042)
  point P163 (-2.6808, 13.2107)
  point P164 (-2.852, 13.4312)
  point P165 (-3.7166, 13.2169)
  point P166 (-3.7659, 12.9411)
  point P167 (-3.7988, 12.6898)
  point P168 (-3.8178, 12.4639)
  point P169 (-3.8252, 12.2642)
  point P170 (-3.8236, 12.0913)
  point P171 (-3.8155, 11.9453)
  point P172 (-3.8032, 11.8267)
  point P173 (-3.7894, 11.7353)
  point P174 (-3.7764, 11.6711)
  point P175 (-3.7668, 11.6336)
  point P176 (-4.8959, 11.2064)
  point P177 (-4.9146, 11.2416)
  point P178 (-4.9482, 11.2989)
  point P179 (-4.9989, 11.3769)
  point P180 (-5.0687, 11.474)
  point P181 (-5.1594, 11.5887)
  point P182 (-5.2728, 11.7191)
  point P183 (-5.4105, 11.8634)
  point P184 (-5.5739, 12.0194)
  point P185 (-5.7645, 12.1851)
  point P186 (-5.9834, 12.3583)
  point P187 (-6.7719, 11.9442)
  point P188 (-6.754, 11.6653)
  point P189 (-6.7261, 11.414)
  point P190 (-6.6907, 11.1906)
  point P191 (-6.6502, 10.9952)
  point P192 (-6.6074, 10.8277)
  point P193 (-6.5645, 10.688)
  point P194 (-6.5241, 10.5755)
  point P195 (-6.4886, 10.4896)
  point P196 (-6.4604, 10.4297)
  point P197 (-6.4418, 10.3948)
  point P198 (-7.4355, 9.709)
  point P199 (-7.4621, 9.7386)
  constraints: 104 end point, 104 point on circle, 55 centre point, 676 other
extrude "Thickness 5 mm" add sketch "Dimensioned base profile" along normal blind 5
sketch "M3 nut sockets AF5.7" plane through (0, 0, 0) normal (0, 0, 1) x (1, 0, 0)
  line L0 (-3.15, 1.6454) -> (-6, 3.2909)
  line L1 (-6, 3.2909) -> (-8.85, 1.6454)
  line L2 (-8.85, 1.6454) -> (-8.85, -1.6454)
  line L3 (-8.85, -1.6454) -> (-6, -3.2909)
  line L4 (-6, -3.2909) -> (-3.15, -1.6454)
  line L5 (-3.15, -1.6454) -> (-3.15, 1.6454)
  line L6 (8.85, 1.6454) -> (6, 3.2909)
  line L7 (6, 3.2909) -> (3.15, 1.6454)
  line L8 (3.15, 1.6454) -> (3.15, -1.6454)
  line L9 (3.15, -1.6454) -> (6, -3.2909)
  line L10 (6, -3.2909) -> (8.85, -1.6454)
  line L11 (8.85, -1.6454) -> (8.85, 1.6454)
  constraints: 24 end point
extrude "Nut sockets depth 2.4" cut sketch "M3 nut sockets AF5.7" along normal blind 2.4
equation "\"NominalThickness\" = 5"
equation "\"Module\" = 1"
body "Solid2"
